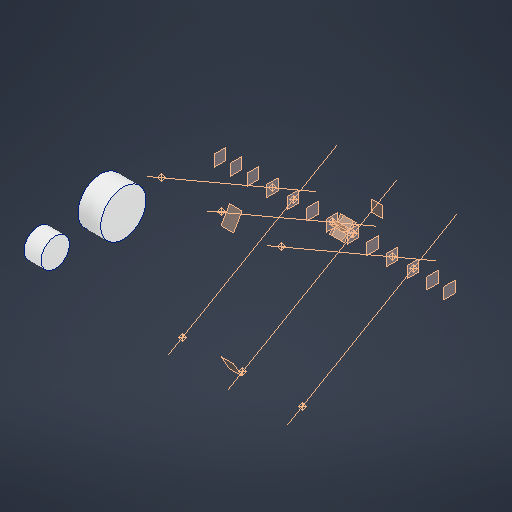
# Autodesk Inventor part: Water_Pump_Thermostat_SIMPLIFIED
Saved by Autodesk Inventor 2027.1 (Build 311270010, 270A)
## iProperties
Created: 2026-10-17
Part Number: Water_Pump_Thermostat_SIMPLIFIED
Material: Aluminum 6061
Document SubType Name: Modeling
Designer: kashyap
Density: 2.7 g/cm^3
Appearance: Aluminum - Flat
Mass: 701.91 g
Surface Area: 287.456 cm^2
Volume: 259.967 cm^3
Material_Status: Assumed for this reconstruction
Author: kashyap
Autodesk Inventor part; units mm, degrees
ref_plane "XZ Plane" through (0, 0, 0) normal (0, 1, 0) x (-1, 0, 0)
ref_plane "XY Plane" through (0, 0, 0) normal (0, 0, 1) x (1, 0, 0)
derived "V6_Engine_Master.ipt"
ref_plane "Bank_A_Plane" through (0, 0, 0) normal (0, 0.8660254, -0.5) x (-1, 0, 0)
ref_plane "Bank_B_Plane" through (0, 0, 0) normal (0, 0.8660254, 0.5) x (-1, 0, 0)
ref_plane "Bank_A_Perp_Plane" through (0, 0, 0) normal (0, 0.5, 0.8660254) x (-1, 0, 0)
ref_plane "Bank_B_Perp_Plane" through (0, 0, 0) normal (0, -0.5, 0.8660254) x (-1, 0, 0)
ref_plane "Bank_A_Deck_Plane" through (0, 112.9, 195.5485) normal (0, 0.5, 0.8660254) x (-1, 0, 0)
ref_plane "Bank_B_Deck_Plane" through (0, -112.9, 195.5485) normal (0, -0.5, 0.8660254) x (-1, 0, 0)
ref_plane "Cyl_A1_Station_Plane" through (-123.8, 0, 0) normal (1, 0, 0) x (0, 1, 0)
ref_plane "Cyl_A2_Station_Plane" through (-18.3, 0, 0) normal (1, 0, 0) x (0, 1, 0)
ref_plane "Cyl_A3_Station_Plane" through (87.2, 0, 0) normal (1, 0, 0) x (0, 1, 0)
ref_plane "Cyl_B1_Station_Plane" through (-87.2, 0, 0) normal (1, 0, 0) x (0, 1, 0)
ref_plane "Cyl_B2_Station_Plane" through (18.3, 0, 0) normal (1, 0, 0) x (0, 1, 0)
ref_plane "Cyl_B3_Station_Plane" through (123.8, 0, 0) normal (1, 0, 0) x (0, 1, 0)
ref_plane "Main_Bearing_Station_1" through (-158.25, 0, 0) normal (1, 0, 0) x (0, 1, 0)
ref_plane "Main_Bearing_Station_2" through (-52.75, 0, 0) normal (1, 0, 0) x (0, 1, 0)
ref_plane "Main_Bearing_Station_3" through (52.75, 0, 0) normal (1, 0, 0) x (0, 1, 0)
ref_plane "Main_Bearing_Station_4" through (158.25, 0, 0) normal (1, 0, 0) x (0, 1, 0)
ref_plane "Front_Interface" through (-188.25, 0, 0) normal (1, 0, 0) x (0, 1, 0)
ref_plane "Rear_Interface" through (188.25, 0, 0) normal (1, 0, 0) x (0, 1, 0)
ref_plane "Oil_Pan_Plane" through (0, 0, -60) normal (0, 0, 1) x (1, 0, 0)
ref_plane "Timing_Cover_Face_Plane" through (-216.25, 0, 0) normal (1, 0, 0) x (0, 1, 0)
sketch "SK_Water_Pump_Body" plane through (-216.25, 0, 0) normal (1, 0, 0) x (0, 1, 0)
  circle A0 centre (0, 170) radius 40
  dimension "d20" = 80
  constraints: 1 centre point
  measures "d20" diameter of A0
extrude "Water_Pump_Body_SIMPLIFIED" add sketch "SK_Water_Pump_Body" against normal blind 40
sketch "SK_Thermostat_Housing" plane through (-216.25, 0, 0) normal (1, 0, 0) x (0, 1, 0)
  circle A0 centre (0, 290) radius 25
  dimension "d25" = 50
  constraints: 1 centre point
  measures "d25" diameter of A0
extrude "Thermostat_Housing_SIMPLIFIED" add sketch "SK_Thermostat_Housing" against normal blind 30
equation "\"d20\" = Water_Pump_Dia"
equation "\"d23\" = Water_Pump_Length"
equation "\"d25\" = Thermostat_Housing_Dia"
equation "\"d28\" = Thermostat_Housing_Length"
equation "\"Water_Pump_Dia\" = 80"
equation "\"Water_Pump_Length\" = 40"
equation "\"Thermostat_Housing_Dia\" = 50"
equation "\"Thermostat_Housing_Length\" = 30"
body "Solid2"
